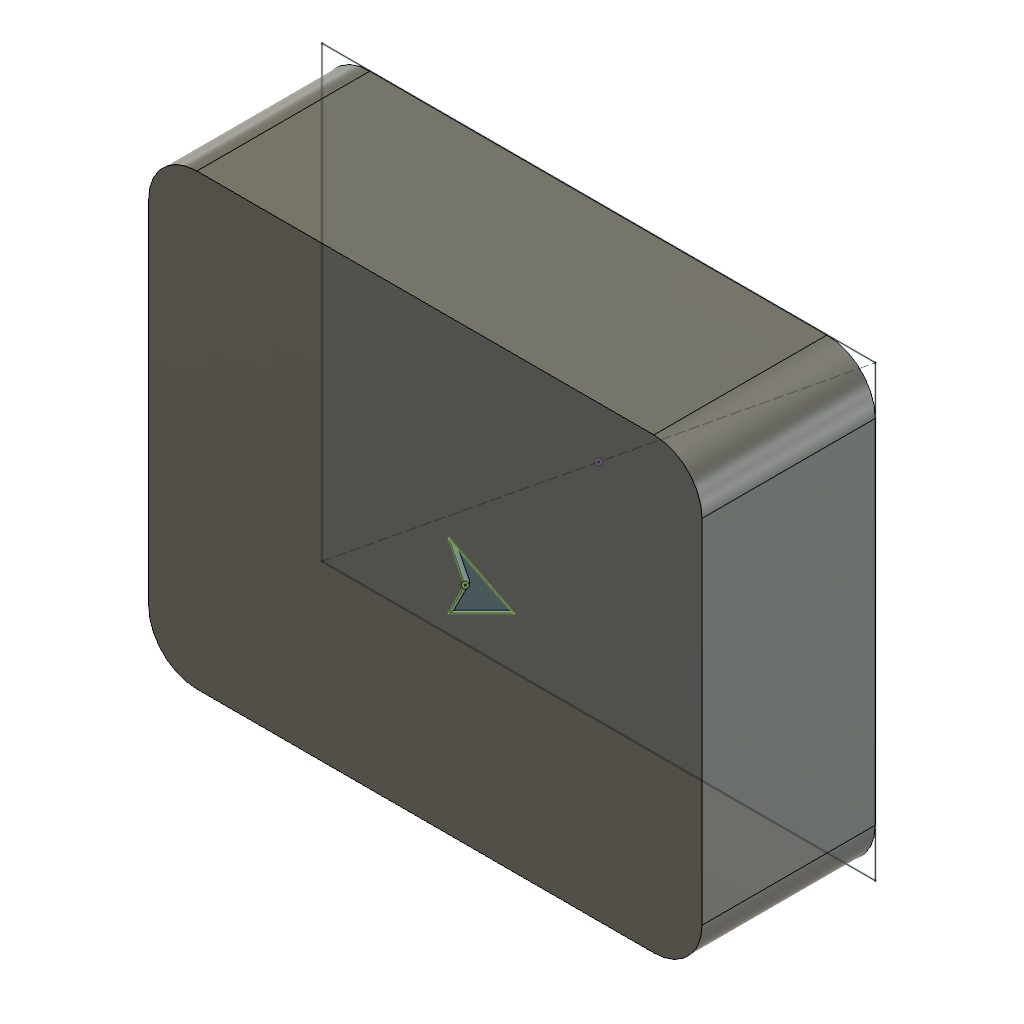
Holybro_Micro_M10 (Autodesk Fusion 360 design; units mm, degrees)
part number: 2026-11-11-15-16-32-870
Autodesk Fusion 360 part; units mm, degrees
sketch "Esquisse_contour_GPS" plane through (0, 0, 0) normal (0, 0, 1) x (1, 0, 0)
  line L0 (-17.225, -13.965) -> (17.225, -13.965)
  line L1 (17.225, -13.965) -> (17.225, 13.965)
  line L2 (17.225, 13.965) -> (-17.225, 13.965)
  line L3 (-17.225, 13.965) -> (-17.225, -13.965)
  line L4 (-17.225, -13.965) -> (17.225, 13.965) construction
  dimension "d7" = 34.45
  dimension "d8" = 27.93
  constraint horizontal L0
  constraint vertical L1
  constraint horizontal L2
  constraint vertical L3
  constraint midpoint origin L4
  measures "d7" horizontal distance of L0.start L0.end
  measures "d8" vertical distance of L0.end L1.end
extrude "Extrusion_GPS" add sketch "Esquisse_contour_GPS" along normal blind 10.79
fillet "Conge_coins" radius 3 4 edges at (-17.225, 13.965, 5.395) (17.225, 13.965, 5.395) (17.225, -13.965, 5.395) (-17.225, -13.965, 5.395)
ref_plane "WorkPlane1" through (0, 0, 10.79) normal (0, 0, 1) x (1, 0, 0)
sketch "Esquisse_fleche" plane through (0, 0, 10.79) normal (0, 0, 1) x (1, 0, 0)
  line L0 (5.5, 0) -> (1.4811, 2.0094)
  line L1 (1.4811, 2.0094) -> (2.4858, 0)
  line L2 (2.4858, 0) -> (1.4811, -2.0094)
  line L3 (1.4811, -2.0094) -> (5.5, 0)
extrude "Gravure_fleche" cut sketch "Esquisse_fleche" against normal blind 0.3
equation "GPS_longueur = 34.45 mm" comment "Longueur, sens de la fleche - MESURE"
equation "GPS_largeur = 27.93 mm" comment "Largeur - MESURE"
equation "GPS_hauteur = 10.79 mm" comment "Hauteur / epaisseur - MESURE"
equation "GPS_rayon_coin = 3.0 mm" comment "Rayon des coins vu de dessus - ESTIME sur photo"
equation "GPS_prof_fleche = 0.3 mm" comment "Profondeur de la fleche de reperage - visuel"
equation "d7 = GPS_longueur"
equation "d8 = GPS_largeur"
equation "d9 = GPS_hauteur"
equation "d12 = GPS_rayon_coin"
equation "d15 = GPS_hauteur"
equation "d17 = -GPS_prof_fleche"
named bodies: "GPS_Micro_M10"
